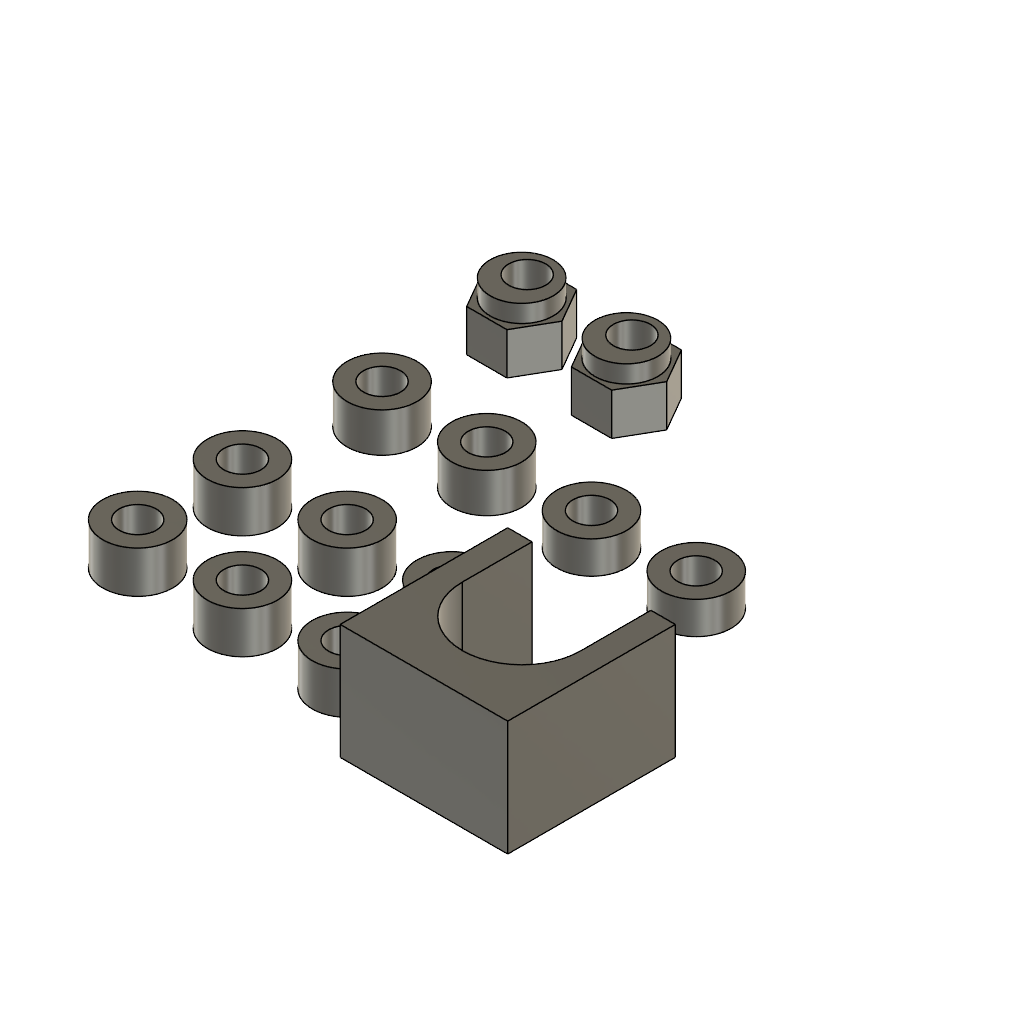
Carriage_Print_Spacers (Autodesk Fusion 360 design; units mm, degrees)
part number: 2026-11-07-00-29-02-465
part number: 2026-11-07-00-29-03-205
part number: 2026-11-07-00-29-03-649
part number: 2026-11-07-00-29-03-778
part number: 2026-11-07-00-29-03-948
part number: 2026-11-07-00-29-04-416
Autodesk Fusion 360 part; units mm, degrees
sketch "Sketch1" plane through (0, 0, 0) normal (0, 0, 1) x (1, 0, 0) in component "Wheel_Spacer_6mm"
  circle A0 centre (0, 0) radius 5
  circle A1 centre (0, 0) radius 2.65
  dimension "d7" = 10
  dimension "d8" = 5.3
  measures "d7" diameter of A0
  measures "d8" diameter of A1
extrude "Extrude1" add sketch "Sketch1" along normal blind 6 makes body 1 in component "Wheel_Spacer_6mm"
sketch "Sketch1 (2)" plane through (0, 0, 0) normal (0, 0, 1) x (1, 0, 0) in component "Idler_Spacer_A_5p64"
  circle A0 centre (0, 0) radius 5
  circle A1 centre (0, 0) radius 2.65
  dimension "d11" = 10
  dimension "d12" = 5.3
  measures "d11" diameter of A0
  measures "d12" diameter of A1
extrude "Extrude1'" add sketch "Sketch1 (2)" along normal blind 5.64 separate body makes body 2 in component "Idler_Spacer_A_5p64"
sketch "Sketch1 (3)" plane through (0, 0, 0) normal (0, 0, 1) x (1, 0, 0) in component "Idler_Spacer_B_4p64"
  circle A0 centre (0, 0) radius 5
  circle A1 centre (0, 0) radius 2.65
  dimension "d15" = 10
  dimension "d16" = 5.3
  measures "d15" diameter of A0
  measures "d16" diameter of A1
extrude "Extrude1''" add sketch "Sketch1 (3)" along normal blind 4.64 separate body makes body 3 in component "Idler_Spacer_B_4p64"
sketch "Sketch1 (4)" plane through (0, 0, 0) normal (0, 0, 1) x (1, 0, 0) in component "Eccentric_Spacer_6mm"
  line L0 (5.7735, 0) -> (2.8868, 5)
  line L1 (2.8868, 5) -> (-2.8868, 5)
  line L2 (-2.8868, 5) -> (-5.7735, 0)
  line L3 (-5.7735, 0) -> (-2.8868, -5)
  line L4 (-2.8868, -5) -> (2.8868, -5)
  line L5 (2.8868, -5) -> (5.7735, 0)
extrude "Extrude1'''" add sketch "Sketch1 (4)" along normal blind 6 separate body makes body 4 in component "Eccentric_Spacer_6mm"
ref_plane "WorkPlane1" through (0, 0, 6) normal (0, 0, 1) x (1, 0, 0) in component "Eccentric_Spacer_6mm"
sketch "Sketch2" plane through (0, 0, 6) normal (0, 0, 1) x (1, 0, 0) in component "Eccentric_Spacer_6mm"
  circle A0 centre (0, 0) radius 4.5
  dimension "d33" = 9
  measures "d33" diameter of A0
extrude "Extrude2" add sketch "Sketch2" along normal blind 2.5 bodies 4 in component "Eccentric_Spacer_6mm"
sketch "Sketch3" plane through (0, 0, 0) normal (0, 0, 1) x (1, 0, 0) in component "Eccentric_Spacer_6mm"
  circle A0 centre (0, 0.79) radius 2.65
  dimension "d34" = 5.3
  measures "d34" diameter of A0
extrude "Extrude3" cut sketch "Sketch3" along normal blind 10 bodies 4 in component "Eccentric_Spacer_6mm"
sketch "Sketch1 (5)" plane through (0, 0, 0) normal (0, 0, 1) x (1, 0, 0) in component "Pulley_Flush_Gauge"
  line L0 (-12, -14) -> (12, -14)
  line L1 (12, -14) -> (12, 10)
  line L2 (12, 10) -> (-12, 10)
  line L3 (-12, 10) -> (-12, -14)
extrude "Extrude1''''" add sketch "Sketch1 (5)" along normal blind 16.5 separate body makes body 5 in component "Pulley_Flush_Gauge"
sketch "Sketch2 (2)" plane through (0, 0, 0) normal (0, 0, 1) x (1, 0, 0) in component "Pulley_Flush_Gauge"
  line L0 (-8.5, 0) -> (8.5, 0)
  line L1 (8.5, 0) -> (8.5, 12)
  line L2 (8.5, 12) -> (-8.5, 12)
  line L3 (-8.5, 12) -> (-8.5, 0)
  circle A0 centre (0, 0) radius 8.5
extrude "Extrude2'" cut sketch "Sketch2 (2)" along normal blind 30 bodies 5 in component "Pulley_Flush_Gauge"
component "Wheel_Spacer_6mm" placed x (1, 0, 0) y (0, 1, 0) z (0, 0, 1) at (0, 0, 0)
component "Idler_Spacer_A_5p64" placed x (1, 0, 0) y (0, 1, 0) z (0, 0, 1) at (0, 35, 0)
component "Idler_Spacer_B_4p64" placed x (1, 0, 0) y (0, 1, 0) z (0, 0, 1) at (30, 35, 0)
component "Eccentric_Spacer_6mm" placed x (1, 0, 0) y (0, 1, 0) z (0, 0, 1) at (0, 55, 0)
component "Pulley_Flush_Gauge" placed x (1, 0, 0) y (0, 1, 0) z (0, 0, 1) at (50, 5, 0)
component "Wheel_Spacer_6mm" placed x (1, 0, 0) y (0, 1, 0) z (0, 0, 1) at (15, 0, 0)
component "Wheel_Spacer_6mm" placed x (1, 0, 0) y (0, 1, 0) z (0, 0, 1) at (30, 0, 0)
component "Wheel_Spacer_6mm" placed x (1, 0, 0) y (0, 1, 0) z (0, 0, 1) at (0, 15, 0)
component "Wheel_Spacer_6mm" placed x (1, 0, 0) y (0, 1, 0) z (0, 0, 1) at (15, 15, 0)
component "Wheel_Spacer_6mm" placed x (1, 0, 0) y (0, 1, 0) z (0, 0, 1) at (30, 15, 0)
component "Idler_Spacer_A_5p64" placed x (1, 0, 0) y (0, 1, 0) z (0, 0, 1) at (15, 35, 0)
component "Idler_Spacer_B_4p64" placed x (1, 0, 0) y (0, 1, 0) z (0, 0, 1) at (45, 35, 0)
component "Eccentric_Spacer_6mm" placed x (1, 0, 0) y (0, 1, 0) z (0, 0, 1) at (15, 55, 0)
equation "Bore = 5.3 mm" comment "M5 bore, +0.2 for FDM undersize"
equation "SpacerOD = 10 mm" comment "spacer OD"
equation "WheelSpacerL = 6 mm" comment "wheel stack spacer length"
equation "IdlerSpacerA = 5.64 mm" comment "idler spacer, plate A side: 12 - idlerW/2"
equation "IdlerSpacerB = 4.64 mm" comment "idler spacer, plate B side: 11 - idlerW/2"
equation "GaugeH = 16.5 mm" comment "pulley flush gauge: 12 + (belt groove centre -> pulley outer face)"
equation "d7 = SpacerOD"
equation "d8 = Bore"
equation "d9 = WheelSpacerL"
equation "d11 = SpacerOD"
equation "d12 = Bore"
equation "d13 = IdlerSpacerA"
equation "d15 = SpacerOD"
equation "d16 = Bore"
equation "d17 = IdlerSpacerB"
equation "d23 = EccRimH"
equation "d27 = GaugeH"
equation "EccRimD = 9 mm" comment "printed eccentric rim (metal part: 7.11). Print plate A hole must be EccRimD + 0.2"
equation "EccRimH = 2.5 mm" comment "rim height into plate A"
equation "d33 = EccRimD"
equation "d34 = Bore"
named bodies: "Wheel_Spacer_6mm", "Idler_Spacer_A_5p64", "Idler_Spacer_B_4p64", "Eccentric_Spacer_6mm", "Pulley_Flush_Gauge"
